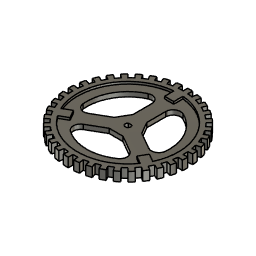
Cansat 轮子 v5 (Autodesk Fusion 360 design; units mm, degrees)
Autodesk Fusion 360 part; units mm, degrees
sketch "草图1" plane through (0, 0, 0) normal (0, 0, 1) x (1, 0, 0)
  line L0 (2.6147, 29.8858) -> (2.8326, 32.3763)
  line L1 (0, 32.5) -> (0, 30)
  arc A0 (2.8326, 32.3763) -> (0, 32.5) centre (0, 0) ccw
  arc A1 (-2.8326, 32.3763) -> (-5.6436, 32.0063) centre (0, 0) ccw
  line L2 (-5.6436, 32.0063) -> (-5.2094, 29.5442)
  line L3 (-2.6147, 29.8858) -> (-2.8326, 32.3763)
  arc A2 (-8.4116, 31.3926) -> (-11.1157, 30.54) centre (0, 0) ccw
  line L4 (-11.1157, 30.54) -> (-10.2606, 28.1908)
  line L5 (-7.7646, 28.9778) -> (-8.4116, 31.3926)
  arc A3 (-13.7351, 29.455) -> (-16.25, 28.1458) centre (0, 0) ccw
  line L6 (-16.25, 28.1458) -> (-15, 25.9808)
  line L7 (-12.6785, 27.1892) -> (-13.7351, 29.455)
  arc A4 (-18.6412, 26.6224) -> (-20.8906, 24.8964) centre (0, 0) ccw
  line L8 (-20.8906, 24.8964) -> (-19.2836, 22.9813)
  line L9 (-17.2073, 24.5746) -> (-18.6412, 26.6224)
  arc A5 (-22.981, 22.981) -> (-24.8964, 20.8906) centre (0, 0) ccw
  line L10 (-24.8964, 20.8906) -> (-22.9813, 19.2836)
  line L11 (-21.2132, 21.2132) -> (-22.981, 22.981)
  arc A6 (-26.6224, 18.6412) -> (-28.1458, 16.25) centre (0, 0) ccw
  line L12 (-28.1458, 16.25) -> (-25.9808, 15)
  line L13 (-24.5746, 17.2073) -> (-26.6224, 18.6412)
  arc A7 (-29.455, 13.7351) -> (-30.54, 11.1157) centre (0, 0) ccw
  line L14 (-30.54, 11.1157) -> (-28.1908, 10.2606)
  line L15 (-27.1892, 12.6785) -> (-29.455, 13.7351)
  arc A8 (-31.3926, 8.4116) -> (-32.0063, 5.6436) centre (0, 0) ccw
  line L16 (-32.0063, 5.6436) -> (-29.5442, 5.2094)
  line L17 (-28.9778, 7.7646) -> (-31.3926, 8.4116)
  arc A9 (-32.3763, 2.8326) -> (-32.5, 0) centre (0, 0) ccw
  line L18 (-32.5, 0) -> (-30, 0)
  line L19 (-29.8858, 2.6147) -> (-32.3763, 2.8326)
  arc A10 (-32.3763, -2.8326) -> (-32.0063, -5.6436) centre (0, 0) ccw
  line L20 (-32.0063, -5.6436) -> (-29.5442, -5.2094)
  line L21 (-29.8858, -2.6147) -> (-32.3763, -2.8326)
  arc A11 (-31.3926, -8.4116) -> (-30.54, -11.1157) centre (0, 0) ccw
  line L22 (-30.54, -11.1157) -> (-28.1908, -10.2606)
  line L23 (-28.9778, -7.7646) -> (-31.3926, -8.4116)
  arc A12 (-29.455, -13.7351) -> (-28.1458, -16.25) centre (0, 0) ccw
  line L24 (-28.1458, -16.25) -> (-25.9808, -15)
  line L25 (-27.1892, -12.6785) -> (-29.455, -13.7351)
  arc A13 (-26.6224, -18.6412) -> (-24.8964, -20.8906) centre (0, 0) ccw
  line L26 (-24.8964, -20.8906) -> (-22.9813, -19.2836)
  line L27 (-24.5746, -17.2073) -> (-26.6224, -18.6412)
  arc A14 (-22.981, -22.981) -> (-20.8906, -24.8964) centre (0, 0) ccw
  line L28 (-20.8906, -24.8964) -> (-19.2836, -22.9813)
  line L29 (-21.2132, -21.2132) -> (-22.981, -22.981)
  arc A15 (-18.6412, -26.6224) -> (-16.25, -28.1458) centre (0, 0) ccw
  line L30 (-16.25, -28.1458) -> (-15, -25.9808)
  line L31 (-17.2073, -24.5746) -> (-18.6412, -26.6224)
  arc A16 (-13.7351, -29.455) -> (-11.1157, -30.54) centre (0, 0) ccw
  line L32 (-11.1157, -30.54) -> (-10.2606, -28.1908)
  line L33 (-12.6785, -27.1892) -> (-13.7351, -29.455)
  arc A17 (-8.4116, -31.3926) -> (-5.6436, -32.0063) centre (0, 0) ccw
  line L34 (-5.6436, -32.0063) -> (-5.2094, -29.5442)
  line L35 (-7.7646, -28.9778) -> (-8.4116, -31.3926)
  arc A18 (-2.8326, -32.3763) -> (0, -32.5) centre (0, 0) ccw
  line L36 (0, -32.5) -> (0, -30)
  line L37 (-2.6147, -29.8858) -> (-2.8326, -32.3763)
  arc A19 (2.8326, -32.3763) -> (5.6436, -32.0063) centre (0, 0) ccw
  line L38 (5.6436, -32.0063) -> (5.2094, -29.5442)
  line L39 (2.6147, -29.8858) -> (2.8326, -32.3763)
  arc A20 (8.4116, -31.3926) -> (11.1157, -30.54) centre (0, 0) ccw
  line L40 (11.1157, -30.54) -> (10.2606, -28.1908)
  line L41 (7.7646, -28.9778) -> (8.4116, -31.3926)
  arc A21 (13.7351, -29.455) -> (16.25, -28.1458) centre (0, 0) ccw
  line L42 (16.25, -28.1458) -> (15, -25.9808)
  line L43 (12.6785, -27.1892) -> (13.7351, -29.455)
  arc A22 (18.6412, -26.6224) -> (20.8906, -24.8964) centre (0, 0) ccw
  line L44 (20.8906, -24.8964) -> (19.2836, -22.9813)
  line L45 (17.2073, -24.5746) -> (18.6412, -26.6224)
  arc A23 (22.981, -22.981) -> (24.8964, -20.8906) centre (0, 0) ccw
  line L46 (24.8964, -20.8906) -> (22.9813, -19.2836)
  line L47 (21.2132, -21.2132) -> (22.981, -22.981)
  arc A24 (26.6224, -18.6412) -> (28.1458, -16.25) centre (0, 0) ccw
  line L48 (28.1458, -16.25) -> (25.9808, -15)
  line L49 (24.5746, -17.2073) -> (26.6224, -18.6412)
  arc A25 (29.455, -13.7351) -> (30.54, -11.1157) centre (0, 0) ccw
  line L50 (30.54, -11.1157) -> (28.1908, -10.2606)
  line L51 (27.1892, -12.6785) -> (29.455, -13.7351)
  arc A26 (31.3926, -8.4116) -> (32.0063, -5.6436) centre (0, 0) ccw
  line L52 (32.0063, -5.6436) -> (29.5442, -5.2094)
  line L53 (28.9778, -7.7646) -> (31.3926, -8.4116)
  arc A27 (32.3763, -2.8326) -> (32.5, 0) centre (0, 0) ccw
  line L54 (32.5, 0) -> (30, 0)
  line L55 (29.8858, -2.6147) -> (32.3763, -2.8326)
  arc A28 (32.3763, 2.8326) -> (32.0063, 5.6436) centre (0, 0) ccw
  line L56 (32.0063, 5.6436) -> (29.5442, 5.2094)
  line L57 (29.8858, 2.6147) -> (32.3763, 2.8326)
  arc A29 (31.3926, 8.4116) -> (30.54, 11.1157) centre (0, 0) ccw
  line L58 (30.54, 11.1157) -> (28.1908, 10.2606)
  line L59 (28.9778, 7.7646) -> (31.3926, 8.4116)
  arc A30 (29.455, 13.7351) -> (28.1458, 16.25) centre (0, 0) ccw
  line L60 (28.1458, 16.25) -> (25.9808, 15)
  line L61 (27.1892, 12.6785) -> (29.455, 13.7351)
  arc A31 (26.6224, 18.6412) -> (24.8964, 20.8906) centre (0, 0) ccw
  line L62 (24.8964, 20.8906) -> (22.9813, 19.2836)
  line L63 (24.5746, 17.2073) -> (26.6224, 18.6412)
  arc A32 (22.981, 22.981) -> (20.8906, 24.8964) centre (0, 0) ccw
  line L64 (20.8906, 24.8964) -> (19.2836, 22.9813)
  line L65 (21.2132, 21.2132) -> (22.981, 22.981)
  arc A33 (18.6412, 26.6224) -> (16.25, 28.1458) centre (0, 0) ccw
  line L66 (16.25, 28.1458) -> (15, 25.9808)
  line L67 (17.2073, 24.5746) -> (18.6412, 26.6224)
  arc A34 (13.7351, 29.455) -> (11.1157, 30.54) centre (0, 0) ccw
  line L68 (11.1157, 30.54) -> (10.2606, 28.1908)
  line L69 (12.6785, 27.1892) -> (13.7351, 29.455)
  arc A35 (8.4116, 31.3926) -> (5.6436, 32.0063) centre (0, 0) ccw
  line L70 (5.6436, 32.0063) -> (5.2094, 29.5442)
  line L71 (7.7646, 28.9778) -> (8.4116, 31.3926)
  arc A36 (5.2094, 29.5442) -> (2.6147, 29.8858) centre (0, 0) ccw
  arc A37 (10.2606, 28.1908) -> (7.7646, 28.9778) centre (0, 0) ccw
  arc A38 (15, 25.9808) -> (12.6785, 27.1892) centre (0, 0) ccw
  arc A39 (19.2836, 22.9813) -> (17.2073, 24.5746) centre (0, 0) ccw
  arc A40 (22.9813, 19.2836) -> (21.2132, 21.2132) centre (0, 0) ccw
  arc A41 (25.9808, 15) -> (24.5746, 17.2073) centre (0, 0) ccw
  arc A42 (28.1908, 10.2606) -> (27.1892, 12.6785) centre (0, 0) ccw
  arc A43 (29.5442, 5.2094) -> (28.9778, 7.7646) centre (0, 0) ccw
  arc A44 (30, 0) -> (29.8858, 2.6147) centre (0, 0) ccw
  arc A45 (29.5442, -5.2094) -> (29.8858, -2.6147) centre (0, 0) ccw
  arc A46 (28.1908, -10.2606) -> (28.9778, -7.7646) centre (0, 0) ccw
  arc A47 (25.9808, -15) -> (27.1892, -12.6785) centre (0, 0) ccw
  arc A48 (22.9813, -19.2836) -> (24.5746, -17.2073) centre (0, 0) ccw
  arc A49 (19.2836, -22.9813) -> (21.2132, -21.2132) centre (0, 0) ccw
  arc A50 (15, -25.9808) -> (17.2073, -24.5746) centre (0, 0) ccw
  arc A51 (10.2606, -28.1908) -> (12.6785, -27.1892) centre (0, 0) ccw
  arc A52 (5.2094, -29.5442) -> (7.7646, -28.9778) centre (0, 0) ccw
  arc A53 (0, -30) -> (2.6147, -29.8858) centre (0, 0) ccw
  arc A54 (-5.2094, -29.5442) -> (-2.6147, -29.8858) centre (0, 0) ccw
  arc A55 (-10.2606, -28.1908) -> (-7.7646, -28.9778) centre (0, 0) ccw
  arc A56 (-15, -25.9808) -> (-12.6785, -27.1892) centre (0, 0) ccw
  arc A57 (-19.2836, -22.9813) -> (-17.2073, -24.5746) centre (0, 0) ccw
  arc A58 (-22.9813, -19.2836) -> (-21.2132, -21.2132) centre (0, 0) ccw
  arc A59 (-25.9808, -15) -> (-24.5746, -17.2073) centre (0, 0) ccw
  arc A60 (-28.1908, -10.2606) -> (-27.1892, -12.6785) centre (0, 0) ccw
  arc A61 (-29.5442, -5.2094) -> (-28.9778, -7.7646) centre (0, 0) ccw
  arc A62 (-30, 0) -> (-29.8858, -2.6147) centre (0, 0) ccw
  arc A63 (-29.5442, 5.2094) -> (-29.8858, 2.6147) centre (0, 0) ccw
  arc A64 (-28.1908, 10.2606) -> (-28.9778, 7.7646) centre (0, 0) ccw
  arc A65 (-25.9808, 15) -> (-27.1892, 12.6785) centre (0, 0) ccw
  arc A66 (-22.9813, 19.2836) -> (-24.5746, 17.2073) centre (0, 0) ccw
  arc A67 (-19.2836, 22.9813) -> (-21.2132, 21.2132) centre (0, 0) ccw
  arc A68 (-15, 25.9808) -> (-17.2073, 24.5746) centre (0, 0) ccw
  arc A69 (-10.2606, 28.1908) -> (-12.6785, 27.1892) centre (0, 0) ccw
  arc A70 (0, 30) -> (-2.6147, 29.8858) centre (0, 0) ccw
  arc A71 (-5.2094, 29.5442) -> (-7.7646, 28.9778) centre (0, 0) ccw
  line L72 (-2.5, 27.3861) -> (-2.5, 22.3861)
  line L73 (-2.5, 22.3861) -> (2.5, 22.3861)
  line L74 (2.5, 22.3861) -> (2.5, 27.3861)
  line L75 (0, 0) -> (0, 36) construction
  line L76 (-22.4671, -15.8581) -> (-18.137, -13.3581)
  line L77 (-18.137, -13.3581) -> (-20.637, -9.028)
  line L78 (-20.637, -9.028) -> (-24.9671, -11.528)
  line L79 (24.9671, -11.528) -> (20.637, -9.028)
  line L80 (20.637, -9.028) -> (18.137, -13.3581)
  line L81 (18.137, -13.3581) -> (22.4671, -15.8581)
  arc A72 (-2.5, 27.3861) -> (-24.9671, -11.528) centre (0, 0) ccw
  arc A73 (-22.4671, -15.8581) -> (22.4671, -15.8581) centre (0, 0) ccw
  arc A74 (24.9671, -11.528) -> (2.5, 27.3861) centre (0, 0) ccw
  dimension "d1" = 65
  dimension "d2" = 60
  dimension "d5" = 360
  dimension "d6" = 55
  dimension "d7" = 5
  dimension "d8" = 5
  dimension "d9" = 5
  dimension "d11" = 360
  constraint coincident A0.centre A1.centre
  constraint concentric A36 A70
  constraint concentric A37 A70
  constraint concentric A38 A70
  constraint concentric A39 A70
  constraint concentric A40 A70
  constraint concentric A41 A70
  constraint concentric A42 A70
  constraint concentric A43 A70
  constraint concentric A44 A70
  constraint concentric A45 A70
  constraint concentric A46 A70
  constraint concentric A47 A70
  constraint concentric A48 A70
  constraint concentric A49 A70
  constraint concentric A50 A70
  constraint concentric A51 A70
  constraint concentric A52 A70
  constraint concentric A53 A70
  constraint concentric A54 A70
  constraint concentric A55 A70
  constraint concentric A56 A70
  constraint concentric A57 A70
  constraint concentric A58 A70
  constraint concentric A59 A70
  constraint concentric A60 A70
  constraint concentric A61 A70
  constraint concentric A62 A70
  constraint concentric A63 A70
  constraint concentric A64 A70
  constraint concentric A65 A70
  constraint concentric A66 A70
  constraint concentric A67 A70
  constraint concentric A68 A70
  constraint concentric A69 A70
  constraint concentric A70 A71
  constraint concentric A54 A72
  constraint vertical L72
  constraint perpendicular L72 L73
  constraint perpendicular L73 L74
  constraint perpendicular L73 L75
  constraint symmetric L72 L74 L75
  constraint concentric A72 A73
  constraint concentric A73 A74
  measures "d1" diameter of A0
  measures "d2" diameter of A70
  measures "d6" diameter of A72
  measures "d7" distance of L72.start L72.end
  measures "d8" distance of L72.end L73.end
  measures "d9" distance of L73.end L74.end
extrude "拉伸1" add sketch "草图1" along normal mid plane 5 makes body 1
sketch "草图2" plane through (0, 0, 0) normal (0, 0, 1) x (1, 0, 0)
  line L0 (0, 0) -> (0, -14) construction
  line L1 (-3.75, -6.4952) -> (3.75, -6.4952)
  line L2 (-7.5, 0) -> (-3.75, 6.4952)
  line L3 (3.75, 6.4952) -> (7.5, 0)
  line L4 (-3.75, 6.4952) -> (-3.75, 16.7984)
  line L5 (3.75, 6.4952) -> (3.75, 16.7984)
  line L6 (0, 0) -> (0, 30.6056) construction
  line L7 (-2.5, 27.3861) -> (-2.5, 22.3861)
  line L8 (-2.5, 22.3861) -> (2.5, 22.3861)
  line L9 (2.5, 22.3861) -> (2.5, 27.3861)
  line L10 (-22.4671, -15.8581) -> (-18.137, -13.3581)
  line L11 (-18.137, -13.3581) -> (-20.637, -9.028)
  line L12 (-20.637, -9.028) -> (-24.9671, -11.528)
  line L13 (24.9671, -11.528) -> (20.637, -9.028)
  line L14 (20.637, -9.028) -> (18.137, -13.3581)
  line L15 (18.137, -13.3581) -> (22.4671, -15.8581)
  arc A0 (-2.5, 27.3861) -> (-24.9671, -11.528) centre (0, 0) ccw
  arc A1 (-22.4671, -15.8581) -> (22.4671, -15.8581) centre (0, 0) ccw
  arc A2 (24.9671, -11.528) -> (2.5, 27.3861) centre (0, 0) ccw
  line L16 (-3.75, -6.4952) -> (-12.6729, -11.6468)
  line L17 (-7.5, 0) -> (-16.4229, -5.1516)
  line L18 (7.5, 0) -> (16.4229, -5.1516)
  line L19 (3.75, -6.4952) -> (12.6729, -11.6468)
  arc A3 (22.4062, -2.0524) -> (9.4257, 20.4305) centre (0, 0) ccw
  arc A4 (-9.4257, 20.4305) -> (-22.4062, -2.0524) centre (0, 0) ccw
  arc A5 (-12.9805, -18.3781) -> (12.9805, -18.3781) centre (0, 0) ccw
  arc A6 (-3.75, 16.7984) -> (-9.4257, 20.4305) centre (-7.75, 16.7984) ccw
  arc A7 (-22.4062, -2.0524) -> (-16.4229, -5.1516) centre (-18.4229, -1.6875) ccw
  arc A8 (9.4257, 20.4305) -> (3.75, 16.7984) centre (7.75, 16.7984) ccw
  arc A9 (16.4229, -5.1516) -> (22.4062, -2.0524) centre (18.4229, -1.6875) ccw
  arc A10 (-12.6729, -11.6468) -> (-12.9805, -18.3781) centre (-10.6729, -15.1109) ccw
  arc A11 (12.9805, -18.3781) -> (12.6729, -11.6468) centre (10.6729, -15.1109) ccw
  line L20 (0, 0) -> (0, 1.15)
  line L21 (0, 1.15) -> (-0.9631, 1.15)
  line L22 (0.9631, 1.15) -> (0, 1.15)
  arc A12 (-0.9631, 1.15) -> (0.9631, 1.15) centre (0, 0) ccw
  dimension "d43" = 55
  dimension "d47" = 5
  dimension "d48" = 5
  dimension "d49" = 5
  dimension "d54" = 45
  dimension "d55" = 4
  dimension "d56" = 4
  dimension "d57" = 4
  dimension "d58" = 4
  dimension "d63" = 3
  dimension "d64" = 1.15
  constraint coincident L0.start L6.start
  constraint vertical L0
  constraint vertical L4
  constraint vertical L7
  constraint perpendicular L7 L8
  constraint perpendicular L8 L9
  constraint symmetric L6 L7 L9
  constraint concentric A0 A1
  constraint concentric A1 A2
  constraint concentric A1 A4
  constraint concentric A3 A4
  constraint concentric A4 A5
  constraint tangent A4 A6
  constraint tangent L4 A6
  constraint tangent A4 A7
  constraint tangent L17 A7
  constraint tangent L5 A8
  constraint tangent A3 A8
  constraint tangent L18 A9
  constraint tangent A3 A9
  constraint tangent L16 A10
  constraint tangent A5 A10
  constraint equal A9 A10
  constraint tangent L19 A11
  constraint tangent A5 A11
  constraint equal A9 A11
  constraint parallel L6 L20
  constraint perpendicular L20 L21
  constraint perpendicular L6 L22
  measures "d43" diameter of A0
  measures "d47" distance of L7.start L7.end
  measures "d48" distance of L7.end L8.end
  measures "d49" distance of L8.end L9.end
  measures "d54" diameter of A4
  measures "d55" radius of A6
  measures "d56" radius of A7
  measures "d57" radius of A8
  measures "d58" radius of A9
  measures "d63" diameter of A12
  measures "d64" distance of L0.start L20.end
extrude "拉伸2" add sketch "草图2" along normal mid plane 2.5 separate body contours L7 L8 L9 L10 L11 L12 L13 L14 L15 A0 A1 A2 | L21 L22 A12 makes body 2
combine "合并1" operation add target body 1 tool bodies 2
extrude "拉伸4" cut sketch "草图2" along normal mid plane 9 contours L21 L22 A12 bodies 1
